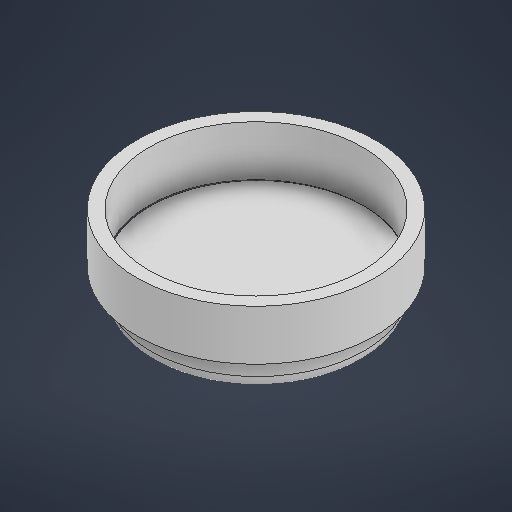
# Autodesk Inventor part: chaveta
Saved by Autodesk Inventor 2026.2 (Build 302298000, 298)
## iProperties
Created: 2026-10-09
Part Number: chaveta
Material: Genérico
Document SubType Name: Modeling
Designer: IFSP
Density: 1 g/cm^3
Appearance: Padrão
Author: IFSP
Autodesk Inventor part; units mm, degrees
ref_plane "YZ Plane" through (0, 0, 0) normal (1, 0, 0) x (0, 1, 0)
ref_plane "XZ Plane" through (0, 0, 0) normal (0, 1, 0) x (-1, 0, 0)
ref_plane "XY Plane" through (0, 0, 0) normal (0, 0, 1) x (1, 0, 0)
sketch "Esboço1" plane through (0, 0, 0) normal (0, 1, 0) x (-1, 0, 0)
  circle A0 centre (0, 0) radius 19
  circle A1 centre (0, 0) radius 17
  circle A2 centre (0, 0) radius 17
  dimension "d0" = 38
  dimension "d1" = 34
  dimension "d2" = 34
  constraints: 3 centre point, 3 coincident
  measures "d0" diameter of A0
  measures "d1" diameter of A1
  measures "d2" diameter of A2
extrude "Extrusão1" add sketch "Esboço1" along normal blind 8
sketch "Esboço2" plane through (0, 0, 0) normal (0, -1, 0) x (1, 0, 0)
  circle A0 centre (0.2056, 0) radius 17
  point P0 (0, 0)
  dimension "d5" = 34
  constraints: 1 centre point
  measures "d5" diameter of A0
extrude "Extrusão2" add sketch "Esboço2" along normal blind 5
fillet "Arredondamento1" radius 2 1 edges at (-16.7944, -5, 0)
